TrigorillaBoardHolder (Autodesk Fusion 360 design; units mm, degrees)
Autodesk Fusion 360 part; units mm, degrees
sketch "Sketch1" plane through (0, 0, 0) normal (0, 1, 0) x (1, 0, 0)
  line L0 (62.525, -41.025) -> (-62.525, -41.025)
  line L1 (-62.525, -41.025) -> (-62.525, 41.025)
  line L2 (-62.525, 41.025) -> (62.525, 41.025)
  line L3 (62.525, 41.025) -> (62.525, -41.025)
  line L4 (62.525, -41.025) -> (-62.525, 41.025) construction
  line L5 (-62.525, -41.025) -> (62.525, 41.025) construction
  dimension "d1" = 82.05
  dimension "d2" = 125.05
  constraint perpendicular L0 L1
  constraint parallel L0 L2
  constraint parallel L1 L3
  constraint horizontal L0
  constraint coincident L4 origin
  constraint coincident L5 origin
  measures "d1" distance of L0.end L1.end
  measures "d2" distance of L1.end L2.end
extrude "Extrude1" add sketch "Sketch1" along normal blind 2
sketch "Sketch2" plane through (0, 2, 0) normal (0, 1, 0) x (-1, 0, 0)
  line L0 (-62.525, -41.025) -> (62.525, -41.025)
  line L1 (62.525, -41.025) -> (62.525, 41.025)
  line L2 (62.525, 41.025) -> (-62.525, 41.025)
  line L3 (-62.525, 41.025) -> (-62.525, -41.025)
  circle A0 centre (-59.025, -37.575) radius 1.7
  line L4 (-59.025, -41.025) -> (-59.025, -37.575)
  line L5 (-62.525, -37.575) -> (-59.025, -37.575)
  line L6 (-59.025, -37.575) -> (-59.025, 37.325)
  circle A1 centre (-59.025, 37.325) radius 1.7
  line L7 (-59.025, 37.325) -> (-45.975, 37.325)
  circle A2 centre (-45.975, 37.325) radius 1.7
  line L8 (-59.025, -37.575) -> (58.975, -37.575)
  circle A3 centre (58.975, -37.575) radius 1.7
  line L9 (-59.025, 37.325) -> (88, 37.325)
  line L10 (58.975, -37.575) -> (58.975, 48)
  circle A4 centre (58.975, 37.325) radius 1.7
  dimension "d10" = 3.4
  dimension "d11" = 3.45
  dimension "d12" = 3.5
  dimension "d13" = 74.9
  dimension "d14" = 3.4
  dimension "d15" = 13.05
  dimension "d16" = 3.4
  dimension "d17" = 118
  dimension "d18" = 3.4
  dimension "d19" = 3.4
  constraint coincident L0 L4.start
  constraint coincident A0.centre L4.end
  constraint coincident L3 L5.start
  constraint coincident L6.end A1.centre
  constraint coincident L7.end A2.centre
  constraint coincident L8.end A3.centre
  constraint perpendicular L1 L9
  constraint perpendicular L2 L10
  constraint coincident L10 A4.centre
  constraint coincident L9 A4.centre
  measures "d10" diameter of A0
  measures "d11" distance of L4.start A0.centre
  measures "d12" distance of L5.start A0.centre
  measures "d13" distance of A0.centre L6.end
  measures "d14" diameter of A1
  measures "d15" distance of L6.end L7.end
  measures "d16" diameter of A2
  measures "d17" distance of A0.centre L8.end
  measures "d18" diameter of A3
  measures "d19" diameter of A4
extrude "Extrude2" cut sketch "Sketch2" against normal up to surface (2 mm away) contours A0 L4 L8 | A0 L4 L5 | A0 L5 L6 | A0 L6 L8 | L9 L10 A4 | L9 L10 A4 | L8 A3 L10 | L8 A3 L10 | L9 L10 A4 | L6 A1 L7 L9 | L6 A1 L7 L9 | L9 L10 A4 | L7 A2 L9 | L7 A2 L9
named bodies: "Trigorilla board template"
